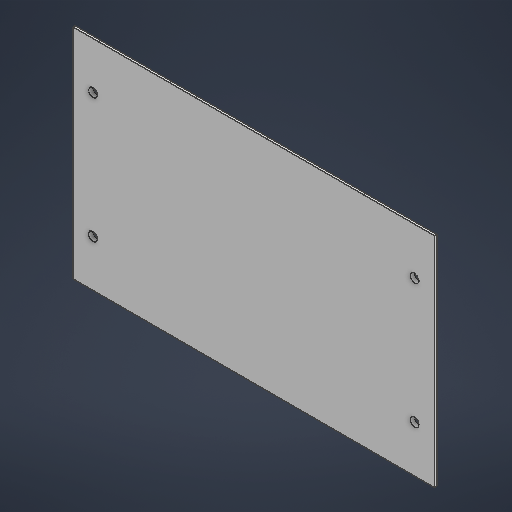
# Autodesk Inventor part: BACK
Saved by Autodesk Inventor 2026.2 (Build 302298010, 298A)
## iProperties
Created: 2026-05-12
Part Number: BACK
Material: 일반
Document SubType Name: Modeling
Designer: work
Density: 1 g/cm^3
Appearance: 기본값
Author: work
Autodesk Inventor part; units mm, degrees
ref_plane "YZ Plane" through (0, 0, 0) normal (1, 0, 0) x (0, 1, 0)
ref_plane "XZ Plane" through (0, 0, 0) normal (0, 1, 0) x (-1, 0, 0)
ref_plane "XY Plane" through (0, 0, 0) normal (0, 0, 1) x (1, 0, 0)
sketch "스케치1" plane through (0, 0, 0) normal (0, 0, 1) x (1, 0, 0)
  line L0 (0, 0) -> (162.5, 0)
  line L1 (162.5, 0) -> (162.5, 98)
  line L2 (162.5, 98) -> (0, 98)
  line L3 (0, 98) -> (0, 0)
  line L4 (81.25, 98) -> (81.25, 0) construction
  line L5 (9, 21) -> (153.5, 21) construction
  line L6 (153.5, 21) -> (153.5, 77) construction
  line L7 (153.5, 77) -> (9, 77) construction
  line L8 (9, 77) -> (9, 21) construction
  line L9 (9, 21) -> (153.5, 77) construction
  line L10 (153.5, 21) -> (9, 77) construction
  circle A0 centre (9, 77) radius 2
  circle A1 centre (153.5, 77) radius 2
  circle A2 centre (153.5, 21) radius 2
  circle A3 centre (9, 21) radius 2
  point P0 (81.25, 49)
  dimension "d0" = 21
  dimension "d1" = 9
  dimension "d2" = 56
  dimension "d3" = 144.5
  dimension "d4" = 4
  dimension "d5" = 4
  dimension "d6" = 4
  dimension "d7" = 4
  constraints: 22 end point, 5 midpoint, 4 centre point, 4 coincident, 4 parallel, 2 horizontal, 2 perpendicular
  measures "d0" distance between parallel lines of L2 L7
  measures "d1" distance between parallel lines of L3 L8
  measures "d2" distance of L7.end L5.start
  measures "d3" distance of L6.end L7.end
  measures "d4" diameter of A0
  measures "d5" diameter of A1
  measures "d6" diameter of A2
  measures "d7" diameter of A3
extrude "돌출1" add sketch "스케치1" along normal blind 2
chamfer "모따기1" distance 1 angle 45 4 edges at (81.25, 98, 0) (0, 49, 0) (81.25, 0, 0) (162.5, 49, 0)
